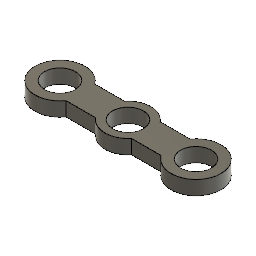
maintiens potentiometre v1 (Autodesk Fusion 360 design; units mm, degrees)
Autodesk Fusion 360 part; units mm, degrees
sketch "Sketch1" plane through (0, 0, 0) normal (0, 1, 0) x (1, 0, 0)
  circle A0 centre (22, 5) radius 2.15
  circle A1 centre (3, 5) radius 2.15
  circle A2 centre (12.5, 5) radius 2.15
  line L0 (5.8589, 7.0191) -> (10, 7.0191)
  line L1 (5.8589, 2.9809) -> (10, 2.9809)
  line L2 (19.1411, 7.0191) -> (15, 7.0191)
  line L3 (19.1411, 2.9809) -> (15, 2.9809)
  arc A3 (15, 7.0191) -> (10, 7.0191) centre (12.5, 5) ccw
  arc A4 (10, 2.9809) -> (15, 2.9809) centre (12.5, 5) ccw
  arc A5 (5.8589, 7.0191) -> (-0.5, 5) centre (3, 5) ccw
  arc A6 (-0.5, 5) -> (5.8589, 2.9809) centre (3, 5) ccw
  arc A7 (25.5, 5) -> (19.1411, 7.0191) centre (22, 5) ccw
  arc A8 (19.1411, 2.9809) -> (25.5, 5) centre (22, 5) ccw
  dimension "d2" = 4.3
  dimension "d3" = 4.3
  dimension "d4" = 4.3
  measures "d2" diameter of A0
  measures "d3" diameter of A1
  measures "d4" diameter of A2
extrude "Extrude1" add sketch "Sketch1" along normal blind 2
